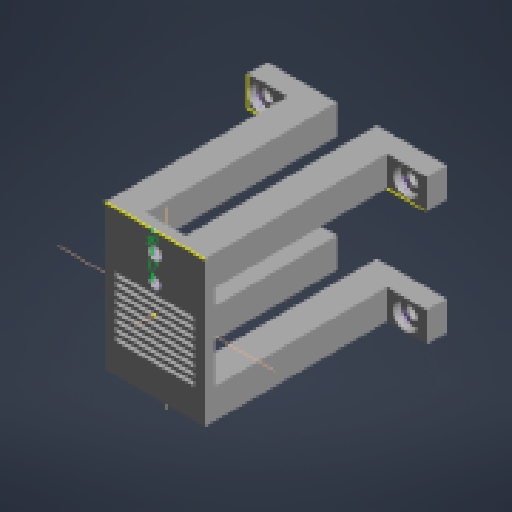
# Autodesk Inventor part: Thermal_Camera_Bracket
Saved by Autodesk Inventor 2027 (Build 310192000, 192)
## iProperties
Created: 2026-11-09
Part Number: Thermal_Camera_Bracket
Material: Genérico
Document SubType Name: Modeling
Designer: Jacob Parker
Density: 1 g/cm^3
Appearance: Valor por defecto
Author: Jacob Parker
Autodesk Inventor part; units mm, degrees
ref_plane "YZ Plane" through (0, 0, 0) normal (1, 0, 0) x (0, 1, 0)
ref_plane "XZ Plane" through (0, 0, 0) normal (0, 1, 0) x (-1, 0, 0)
ref_plane "XY Plane" through (0, 0, 0) normal (0, 0, 1) x (1, 0, 0)
sketch "baseSK" plane through (0, 0, 0) normal (0, 0, 1) x (1, 0, 0)
  line L0 (25, 36.5) -> (-25, 36.5)
  line L1 (-25, 36.5) -> (-25, -36.5)
  line L2 (-25, -36.5) -> (25, -36.5)
  line L3 (25, -36.5) -> (25, 36.5)
  point P0 (0, 0)
  dimension "d0" = 50
  dimension "d1" = 73
  dimension "d2" = 36.5
  dimension "d3" = 25
  constraints: 8 end point, 2 parallel, 1 horizontal, 1 perpendicular
  measures "d0" distance of L1.end L2.end
  measures "d1" distance of L0.end L1.end
  measures "d2" distance from line of point (0, 0) L2
  measures "d3" distance from line of point (0, 0) L1
extrude "baseEX" add sketch "baseSK" along normal blind 5.5
sketch "holeSk" plane through (0, 0, 5.5) normal (0, 0, 1) x (1, 0, 0)
  line L0 (25, 36.5) -> (-25, 36.5) projected
  point P0 (0, 0)
  point P1 (0, 26.5)
  point P2 (0, 13.5)
  point P3 (0, 36.5)
  dimension "d13" = 13
  dimension "d14" = 10
  constraints: 1 midpoint
  measures "d13" distance of point (0, 26.5) point (0, 13.5)
  measures "d14" distance of point (0, 36.5) point (0, 26.5)
hole "bigH" at (0, 26.5, 5.5) direction (0, 0, -1) diameter 7 depth 8
hole "smallH" at (0, 13.5, 5.5) direction (0, 0, -1) diameter 6 depth 8
sketch "Sketch6" plane through (0, 0, 0) normal (0, 0, -1) x (-1, 0, 0)
  line L0 (25, 36.5) -> (10, 36.5)
  line L1 (10, 36.5) -> (10, 21.5)
  line L2 (10, 21.5) -> (25, 21.5)
  line L3 (25, 21.5) -> (25, 36.5)
  line L4 (0, -51.1) -> (0, 51.1) projected
  line L5 (35, 0) -> (-35, 0) projected
  line L6 (-25, 36.5) -> (-10, 36.5)
  line L7 (-10, 36.5) -> (-10, 21.5)
  line L8 (-10, 21.5) -> (-25, 21.5)
  line L9 (-25, 21.5) -> (-25, 36.5)
  line L10 (-35, 0) -> (35, 0)
  line L11 (25, -36.5) -> (10, -36.5)
  line L12 (10, -36.5) -> (10, -21.5)
  line L13 (10, -21.5) -> (25, -21.5)
  line L14 (25, -21.5) -> (25, -36.5)
  line L15 (-25, -36.5) -> (-10, -36.5)
  line L16 (-10, -36.5) -> (-10, -21.5)
  line L17 (-10, -21.5) -> (-25, -21.5)
  line L18 (-25, -21.5) -> (-25, -36.5)
  point P0 (0, 0)
  dimension "d29" = 15
  dimension "d30" = 15
  constraints: 34 end point, 13 symmetric about line, 2 parallel, 1 horizontal, 1 perpendicular
  measures "d29" distance of L2.end L1.end
  measures "d30" distance of L0.end L1.end
extrude "Extrusion3" add sketch "Sketch6" along normal blind 96.1
sketch "Sketch7" plane through (25, -36.5, 5.5) normal (1, 0, 0) x (0, 0, -1)
  line L0 (101.6, 15) -> (101.6, 0) projected
  line L1 (101.6, 0) -> (0, 0) projected
  line L2 (101.6, 15) -> (91.6, 15)
  line L3 (91.6, 15) -> (91.6, 0)
  line L4 (91.6, 0) -> (101.6, 0)
  line L5 (101.6, 0) -> (101.6, 15)
  point P0 (5.5, 36.5)
  dimension "d33" = 10
  constraints: 8 end point, 2 parallel, 1 horizontal, 1 perpendicular, 1 point on line
  measures "d33" distance of L4.end L3.end
extrude "Extrusion4" add sketch "Sketch7" along normal blind 20
sketch "Sketch10" plane through (0, 0, 5.5) normal (0, 0, 1) x (1, 0, 0)
  line L0 (20, -21.5) -> (-20, -21.5)
  line L1 (-20, -21.5) -> (-20, -19.5)
  line L2 (-20, -19.5) -> (20, -19.5)
  line L3 (20, -19.5) -> (20, -21.5)
  line L4 (-25, 21.5) -> (-25, -21.5) projected
  line L5 (-20, -21.5) -> (-25, -21.5)
  line L6 (20, -21.5) -> (25, -21.5)
  line L7 (20, -17.5) -> (-20, -17.5)
  line L8 (-20, -17.5) -> (-20, -15.5)
  line L9 (-20, -15.5) -> (20, -15.5)
  line L10 (20, -15.5) -> (20, -17.5)
  line L11 (20, -13.5) -> (-20, -13.5)
  line L12 (-20, -13.5) -> (-20, -11.5)
  line L13 (-20, -11.5) -> (20, -11.5)
  line L14 (20, -11.5) -> (20, -13.5)
  line L15 (20, -9.5) -> (-20, -9.5)
  line L16 (-20, -9.5) -> (-20, -7.5)
  line L17 (-20, -7.5) -> (20, -7.5)
  line L18 (20, -7.5) -> (20, -9.5)
  line L19 (20, -5.5) -> (-20, -5.5)
  line L20 (-20, -5.5) -> (-20, -3.5)
  line L21 (-20, -3.5) -> (20, -3.5)
  line L22 (20, -3.5) -> (20, -5.5)
  line L23 (20, -1.5) -> (-20, -1.5)
  line L24 (-20, -1.5) -> (-20, 0.5)
  line L25 (-20, 0.5) -> (20, 0.5)
  line L26 (20, 0.5) -> (20, -1.5)
  line L27 (20, 2.5) -> (-20, 2.5)
  line L28 (-20, 2.5) -> (-20, 4.5)
  line L29 (-20, 4.5) -> (20, 4.5)
  line L30 (20, 4.5) -> (20, 2.5)
  line L31 (20, 6.5) -> (-20, 6.5)
  line L32 (-20, 6.5) -> (-20, 8.5)
  line L33 (-20, 8.5) -> (20, 8.5)
  line L34 (20, 8.5) -> (20, 6.5)
  point P0 (0, 0)
  dimension "d49" = 40
  dimension "d50" = 2
  dimension "d56" = 4
  constraints: 68 end point, 2 collinear, 2 horizontal, 2 parallel, 1 perpendicular, 1 vertical, 55 other
  measures "d49" distance of L0.start L0.end
  measures "d50" distance of L0.end L1.end
  measures "d56" distance of L0.start L7.start
extrude "Extrusion6" cut sketch "Sketch10" against normal blind 20
pattern_linear "Rectangular Pattern1" count 2 spacing 70 along (-1, 0, 0) count 2 spacing 58 along (0, 1, 0) of "Extrusion4"
sketch "Sketch11" plane through (-45, 21.5, -86.1) normal (0, 0, 1) x (1, 0, 0)
  line L0 (0, 0) -> (20, 0) projected
  line L1 (0, 15) -> (0, 0) projected
  line L2 (70, 0) -> (90, 0) projected
  line L3 (0, -43) -> (0, -58) projected
  point P0 (45, -21.5)
  point P1 (6.8765, 7.0324)
  point P2 (79.4904, -51.0651)
  point P3 (7.3441, -50.1883)
  point P4 (79.7143, 7.3826)
hole "Hole3" at (-38.1235, 28.5324, -86.1) at (34.7143, 28.8826, -86.1) at (34.4904, -29.5651, -86.1) at (-37.6559, -28.6883, -86.1) direction (0, 0, -1) diameter 7 end through all
hole "Hole4" at (34.4904, -29.5651, -86.1) at (34.7143, 28.8826, -86.1) at (-38.1235, 28.5324, -86.1) at (-37.6559, -28.6883, -86.1) direction (0, 0, -1) diameter 13 depth 4
shell "Shell2" thickness 1 removed faces 4 at (-18.0605, -29.0367, -96.1) at (-18.2163, 28.9848, -96.1) at (17.0799, 29.1015, -96.1) at (17.0053, -29.0477, -96.1)
equation "\"d2\" = 0.5 * d1"
equation "\"d3\" = 0.5 * d0"
equation "\"d29\" = d30"
body "Solid1"
